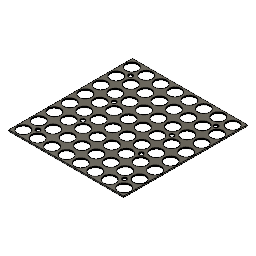
8x8_pcb_mask (Autodesk Fusion 360 design; units mm, degrees)
Autodesk Fusion 360 part; units mm, degrees
(part 1 of 18)
sketch "8x8-User_Comments" plane through (0, 0, 0) normal (0, 0, 1) x (1, 0, 0)
  line L0 (60.8107, -104.03) -> (61.1472, -104.007)
  line L1 (151.386, -103.077) -> (151.151, -103.327)
  line L2 (148.966, -104.174) -> (148.623, -104.148)
  line L3 (58.4649, -102.896) -> (58.6866, -103.15)
  line L4 (151.941, -100.763) -> (151.883, -100.431)
  line L5 (152.029, -100.419) -> (152.086, -100.757)
  line L6 (57.7053, -101.057) -> (57.7087, -101.008)
  line L7 (149.732, -98.1062) -> (150.062, -98.2032)
  line L8 (147.186, -103.377) -> (147.46, -103.574)
  line L9 (149.397, -104.007) -> (149.729, -103.945)
  line L10 (63.1322, -102.847) -> (63.3174, -102.565)
  line L11 (150.605, -103.741) -> (150.3, -103.9)
  line L12 (57.7292, -100.715) -> (57.7912, -100.377)
  line L13 (149.061, -104.03) -> (149.397, -104.007)
  line L14 (150.36, -103.711) -> (150.651, -103.54)
  line L15 (149.051, -98.0251) -> (149.394, -98.0466)
  line L16 (59.8164, -103.867) -> (60.1409, -103.959)
  line L17 (146.879, -98.903) -> (147.137, -98.6769)
  line L18 (146.937, -103.15) -> (147.186, -103.377)
  line L19 (147.46, -103.574) -> (147.755, -103.738)
  line L20 (149.648, -104.112) -> (149.309, -104.162)
  line L21 (146.243, -102.005) -> (146.366, -102.32)
  line L22 (63.7042, -101.284) -> (63.71, -101.1)
  line L23 (147.644, -103.845) -> (147.346, -103.673)
  line L24 (63.71, -101.1) -> (63.6905, -100.763)
  line L25 (152.086, -100.757) -> (152.105, -101.1)
  line L26 (148.066, -103.867) -> (148.391, -103.959)
  line L27 (57.9886, -102.39) -> (57.8622, -102.071)
  line L28 (146.524, -102.618) -> (146.715, -102.896)
  line L29 (150.957, -98.7035) -> (151.212, -98.9333)
  line L30 (60.1409, -103.959) -> (60.4737, -104.014)
  line L31 (62.4014, -103.54) -> (62.6712, -103.338)
  line L32 (146.445, -99.4342) -> (146.647, -99.1565)
  line L33 (59.2101, -103.574) -> (59.5048, -103.738)
  line L34 (151.638, -99.4705) -> (151.803, -99.7713)
  line L35 (151.765, -102.506) -> (151.591, -102.802)
  line L36 (58.3437, -102.976) -> (58.1498, -102.693)
  line L37 (149.729, -103.945) -> (150.051, -103.846)
  line L38 (146.715, -102.896) -> (146.937, -103.15)
  line L39 (147.958, -103.982) -> (147.644, -103.845)
  line L40 (63.3174, -102.565) -> (63.469, -102.264)
  line L41 (61.9717, -98.4234) -> (61.6562, -98.3041)
  line L42 (152.104, -101.186) -> (152.075, -101.528)
  line L43 (57.8515, -101.008) -> (57.8603, -101.345)
  line L44 (151.567, -102.565) -> (151.719, -102.264)
  line L45 (150.921, -103.338) -> (151.166, -103.106)
  line L46 (57.8622, -102.071) -> (57.7722, -101.739)
  line L47 (145.955, -101.057) -> (145.959, -101.008)
  line L48 (150.062, -98.2032) -> (150.378, -98.3362)
  line L49 (146.818, -103.236) -> (146.594, -102.976)
  line L50 (60.3217, -98.2061) -> (59.9921, -98.278)
  line L51 (62.1102, -103.711) -> (62.4014, -103.54)
  line L52 (58.1978, -99.7154) -> (58.0558, -100.021)
  line L53 (63.469, -102.264) -> (63.5849, -101.947)
  line L54 (151.954, -101.284) -> (151.96, -101.1)
  line L55 (146.022, -101.739) -> (145.97, -101.4)
  line L56 (150.889, -103.549) -> (150.605, -103.741)
  line L57 (59.9921, -98.278) -> (59.6729, -98.3872)
  line L58 (150.378, -98.3362) -> (150.678, -98.5037)
  line L59 (146.647, -99.1565) -> (146.879, -98.903)
  line L60 (146.366, -102.32) -> (146.524, -102.618)
  line L61 (147.755, -103.738) -> (148.066, -103.867)
  line L62 (58.8195, -98.9226) -> (58.5822, -99.1624)
  line L63 (57.9078, -101.679) -> (57.9934, -102.005)
  line L64 (57.8815, -100.672) -> (57.8515, -101.008)
  line L65 (151.96, -101.1) -> (151.941, -100.763)
  line L66 (61.4789, -103.945) -> (61.8013, -103.846)
  line L67 (145.959, -101.008) -> (145.979, -100.715)
  line L68 (150.651, -103.54) -> (150.921, -103.338)
  line L69 (63.4044, -99.7972) -> (63.2373, -99.5042)
  line L70 (62.2715, -98.5781) -> (61.9717, -98.4234)
  line L71 (148.37, -98.0967) -> (148.709, -98.0418)
  line L72 (151.787, -100.108) -> (151.654, -99.7972)
  line L73 (146.14, -100.048) -> (146.276, -99.7327)
  line L74 (152.105, -101.1) -> (152.104, -101.186)
  line L75 (147.346, -103.673) -> (147.07, -103.469)
  line L76 (63.0376, -99.2324) -> (62.8079, -98.9853)
  line L77 (150.3, -103.9) -> (149.98, -104.024)
  line L78 (147.07, -103.469) -> (146.818, -103.236)
  line L79 (148.709, -98.0418) -> (149.051, -98.0251)
  line L80 (151.591, -102.802) -> (151.386, -103.077)
  line L81 (148.391, -103.959) -> (148.724, -104.014)
  line L82 (58.0558, -100.021) -> (57.9499, -100.342)
  line L83 (59.3685, -98.5325) -> (59.0827, -98.7117)
  line L84 (146.239, -102.39) -> (146.112, -102.071)
  line L85 (146.4, -102.693) -> (146.239, -102.39)
  line L86 (58.116, -102.32) -> (58.2738, -102.618)
  line L87 (148.724, -104.014) -> (149.061, -104.03)
  line L88 (146.041, -100.377) -> (146.14, -100.048)
  line L89 (58.6866, -103.15) -> (58.9361, -103.377)
  line L90 (59.5048, -103.738) -> (59.8164, -103.867)
  line L91 (147.137, -98.6769) -> (147.419, -98.4809)
  line L92 (59.6729, -98.3872) -> (59.3685, -98.5325)
  line L93 (149.394, -98.0466) -> (149.732, -98.1062)
  line L94 (60.9946, -98.1779) -> (60.6573, -98.1726)
  line L95 (151.914, -101.619) -> (151.954, -101.284)
  line L96 (57.7722, -101.739) -> (57.7197, -101.4)
  line L97 (146.594, -102.976) -> (146.4, -102.693)
  line L98 (151.934, -100.089) -> (152.029, -100.419)
  line L99 (58.1498, -102.693) -> (57.9886, -102.39)
  line L100 (63.6905, -100.763) -> (63.6325, -100.431)
  line L101 (151.151, -103.327) -> (150.889, -103.549)
  line L102 (62.6712, -103.338) -> (62.9158, -103.106)
  line L103 (151.44, -99.19) -> (151.638, -99.4705)
  line L104 (63.2373, -99.5042) -> (63.0376, -99.2324)
  line L105 (57.9934, -102.005) -> (58.116, -102.32)
  line L106 (148.623, -104.148) -> (148.286, -104.084)
  line L107 (150.678, -98.5037) -> (150.957, -98.7035)
  line L108 (151.719, -102.264) -> (151.835, -101.947)
  line L109 (151.212, -98.9333) -> (151.44, -99.19)
  line L110 (146.112, -102.071) -> (146.022, -101.739)
  line L111 (60.4737, -104.014) -> (60.8107, -104.03)
  line L112 (152.008, -101.865) -> (151.905, -102.192)
  line L113 (58.2738, -102.618) -> (58.4649, -102.896)
  line L114 (152.075, -101.528) -> (152.008, -101.865)
  line L115 (145.97, -101.4) -> (145.955, -101.057)
  line L116 (63.5849, -101.947) -> (63.6637, -101.619)
  line L117 (63.6325, -100.431) -> (63.5367, -100.108)
  line L118 (151.905, -102.192) -> (151.765, -102.506)
  line L119 (63.5367, -100.108) -> (63.4044, -99.7972)
  line L120 (57.8603, -101.345) -> (57.9078, -101.679)
  line L121 (148.286, -104.084) -> (147.958, -103.982)
  line L122 (147.721, -98.3177) -> (148.039, -98.1891)
  line L123 (60.6573, -98.1726) -> (60.3217, -98.2061)
  line L124 (148.039, -98.1891) -> (148.37, -98.0967)
  line L125 (146.276, -99.7327) -> (146.445, -99.4342)
  line L126 (149.98, -104.024) -> (149.648, -104.112)
  line L127 (151.835, -101.947) -> (151.914, -101.619)
  line L128 (151.883, -100.431) -> (151.787, -100.108)
  line L129 (62.5514, -98.7662) -> (62.2715, -98.5781)
  line L130 (58.5822, -99.1624) -> (58.3741, -99.4278)
  line L131 (151.166, -103.106) -> (151.382, -102.847)
  line L132 (58.3741, -99.4278) -> (58.1978, -99.7154)
  line L133 (62.9158, -103.106) -> (63.1322, -102.847)
  line L134 (149.309, -104.162) -> (148.966, -104.174)
  line L135 (145.979, -100.715) -> (146.041, -100.377)
  line L136 (61.1472, -104.007) -> (61.4789, -103.945)
  line L137 (146.158, -101.679) -> (146.243, -102.005)
  line L138 (147.419, -98.4809) -> (147.721, -98.3177)
  line L139 (63.6637, -101.619) -> (63.7042, -101.284)
  line L140 (58.9361, -103.377) -> (59.2101, -103.574)
  line L141 (151.382, -102.847) -> (151.567, -102.565)
  line L142 (57.9499, -100.342) -> (57.8815, -100.672)
  line L143 (61.6562, -98.3041) -> (61.329, -98.2219)
  line L144 (61.329, -98.2219) -> (60.9946, -98.1779)
  line L145 (151.803, -99.7713) -> (151.934, -100.089)
  line L146 (150.051, -103.846) -> (150.36, -103.711)
  line L147 (62.8079, -98.9853) -> (62.5514, -98.7662)
  line L148 (57.7087, -101.008) -> (57.7292, -100.715)
  line L149 (61.8013, -103.846) -> (62.1102, -103.711)
  line L150 (59.0827, -98.7117) -> (58.8195, -98.9226)
  line L151 (57.7197, -101.4) -> (57.7053, -101.057)
  line L152 (169.271, -52.4277) -> (169.589, -52.2991)
  line L153 (172.155, -57.8513) -> (171.85, -58.0104)
  line L154 (167.591, -54.4869) -> (167.69, -54.1583)
  line L155 (172.936, -57.1866) -> (172.701, -57.4368)
  line L156 (150.801, -98.7662) -> (150.521, -98.5781)
  line L157 (148.242, -98.278) -> (147.923, -98.3872)
  line L158 (167.505, -55.1671) -> (167.509, -55.118)
  line L159 (173.654, -55.2959) -> (173.625, -55.638)
  line L160 (173.484, -54.1987) -> (173.579, -54.5287)
  line L161 (151.288, -99.2324) -> (151.058, -98.9853)
  line L162 (146.306, -100.021) -> (146.2, -100.342)
  line L163 (169.508, -58.0921) -> (169.194, -57.9547)
  line L164 (173.353, -53.8813) -> (173.484, -54.1987)
  line L165 (150.521, -98.5781) -> (150.222, -98.4234)
  line L166 (170.173, -58.258) -> (169.836, -58.1937)
  line L167 (171.612, -52.3132) -> (171.928, -52.4462)
  line L168 (167.662, -56.1806) -> (167.572, -55.8493)
  line L169 (173.558, -55.9747) -> (173.455, -56.302)
  line L170 (171.53, -58.1345) -> (171.198, -58.2222)
  line L171 (167.995, -53.5442) -> (168.197, -53.2665)
  line L172 (169.194, -57.9547) -> (168.896, -57.783)
  line L173 (149.906, -98.3041) -> (149.579, -98.2219)
  line L174 (168.969, -52.5909) -> (169.271, -52.4277)
  line L175 (146.448, -99.7154) -> (146.306, -100.021)
  line L176 (168.197, -53.2665) -> (168.429, -53.013)
  line L177 (168.687, -52.7869) -> (168.969, -52.5909)
  line L178 (149.245, -98.1779) -> (148.907, -98.1726)
  line L179 (167.69, -54.1583) -> (167.826, -53.8427)
  line L180 (171.198, -58.2222) -> (170.859, -58.2723)
  line L181 (171.928, -52.4462) -> (172.228, -52.6137)
  line L182 (170.259, -52.1518) -> (170.601, -52.1351)
  line L183 (172.507, -52.8135) -> (172.762, -53.0433)
  line L184 (167.95, -56.8029) -> (167.789, -56.4998)
  line L185 (173.579, -54.5287) -> (173.636, -54.8672)
  line L186 (172.99, -53.3) -> (173.188, -53.5805)
  line L187 (146.2, -100.342) -> (146.131, -100.672)
  line L188 (167.793, -56.1154) -> (167.916, -56.4297)
  line L189 (148.907, -98.1726) -> (148.572, -98.2061)
  line L190 (147.923, -98.3872) -> (147.618, -98.5325)
  line L191 (146.832, -99.1624) -> (146.624, -99.4278)
  line L192 (170.516, -58.2843) -> (170.173, -58.258)
  line L193 (173.188, -53.5805) -> (173.353, -53.8813)
  line L194 (173.315, -56.6156) -> (173.141, -56.9117)
  line L195 (173.625, -55.638) -> (173.558, -55.9747)
  line L196 (167.572, -55.8493) -> (167.52, -55.5101)
  line L197 (173.655, -55.21) -> (173.654, -55.2959)
  line L198 (167.826, -53.8427) -> (167.995, -53.5442)
  line L199 (167.916, -56.4297) -> (168.074, -56.7278)
  line L200 (146.624, -99.4278) -> (146.448, -99.7154)
  line L201 (171.85, -58.0104) -> (171.53, -58.1345)
  line L202 (150.222, -98.4234) -> (149.906, -98.3041)
  line L203 (172.762, -53.0433) -> (172.99, -53.3)
  line L204 (167.708, -55.7891) -> (167.793, -56.1154)
  line L205 (151.058, -98.9853) -> (150.801, -98.7662)
  line L206 (167.789, -56.4998) -> (167.662, -56.1806)
  line L207 (168.144, -57.0862) -> (167.95, -56.8029)
  line L208 (168.265, -57.0058) -> (168.487, -57.26)
  line L209 (169.836, -58.1937) -> (169.508, -58.0921)
  line L210 (168.62, -57.5793) -> (168.368, -57.3461)
  line L211 (146.131, -100.672) -> (146.101, -101.008)
  line L212 (170.601, -52.1351) -> (170.944, -52.1566)
  line L213 (168.896, -57.783) -> (168.62, -57.5793)
  line L214 (146.11, -101.345) -> (146.158, -101.679)
  line L215 (147.333, -98.7117) -> (147.069, -98.9226)
  line L216 (168.074, -56.7278) -> (168.265, -57.0058)
  line L217 (168.429, -53.013) -> (168.687, -52.7869)
  line L218 (173.636, -54.8672) -> (173.655, -55.21)
  line L219 (149.579, -98.2219) -> (149.245, -98.1779)
  line L220 (172.439, -57.6593) -> (172.155, -57.8513)
  line L221 (147.618, -98.5325) -> (147.333, -98.7117)
  line L222 (168.368, -57.3461) -> (168.144, -57.0862)
  line L223 (151.487, -99.5042) -> (151.288, -99.2324)
  line L224 (169.92, -52.2067) -> (170.259, -52.1518)
  line L225 (151.654, -99.7972) -> (151.487, -99.5042)
  line L226 (167.52, -55.5101) -> (167.505, -55.1671)
  line L227 (148.572, -98.2061) -> (148.242, -98.278)
  line L228 (147.069, -98.9226) -> (146.832, -99.1624)
  line L229 (167.529, -54.8246) -> (167.591, -54.4869)
  line L230 (146.101, -101.008) -> (146.11, -101.345)
  line L231 (169.589, -52.2991) -> (169.92, -52.2067)
  line L232 (172.228, -52.6137) -> (172.507, -52.8135)
  line L233 (172.701, -57.4368) -> (172.439, -57.6593)
  line L234 (171.282, -52.2162) -> (171.612, -52.3132)
  line L235 (170.944, -52.1566) -> (171.282, -52.2162)
  line L236 (167.509, -55.118) -> (167.529, -54.8246)
  line L237 (173.455, -56.302) -> (173.315, -56.6156)
  line L238 (170.859, -58.2723) -> (170.516, -58.2843)
  line L239 (173.141, -56.9117) -> (172.936, -57.1866)
  line L240 (173.51, -55.21) -> (173.491, -54.8732)
  line L241 (168.736, -57.487) -> (169.01, -57.6838)
  line L242 (172.838, -53.3424) -> (172.608, -53.0953)
  line L243 (172.608, -53.0953) -> (172.351, -52.8762)
  line L244 (173.491, -54.8732) -> (173.433, -54.5409)
  line L245 (168.487, -57.26) -> (168.736, -57.487)
  line L246 (173.269, -56.3736) -> (173.385, -56.0569)
  line L247 (169.01, -57.6838) -> (169.305, -57.8479)
  line L248 (172.201, -57.6504) -> (172.471, -57.4479)
  line L249 (172.716, -57.2157) -> (172.932, -56.9569)
  line L250 (173.464, -55.7289) -> (173.504, -55.394)
  line L251 (173.504, -55.394) -> (173.51, -55.21)
  line L252 (172.471, -57.4479) -> (172.716, -57.2157)
  line L253 (173.117, -56.675) -> (173.269, -56.3736)
  line L254 (171.601, -57.9562) -> (171.91, -57.8206)
  line L255 (173.385, -56.0569) -> (173.464, -55.7289)
  line L256 (169.305, -57.8479) -> (169.616, -57.977)
  line L257 (172.071, -52.6881) -> (171.772, -52.5334)
  line L258 (172.932, -56.9569) -> (173.117, -56.675)
  line L259 (173.337, -54.2175) -> (173.204, -53.9072)
  line L260 (173.204, -53.9072) -> (173.037, -53.6142)
  line L261 (171.91, -57.8206) -> (172.201, -57.6504)
  line L262 (170.611, -58.1398) -> (170.947, -58.1169)
  line L263 (169.941, -58.0694) -> (170.274, -58.1239)
  line L264 (170.274, -58.1239) -> (170.611, -58.1398)
  line L265 (173.433, -54.5409) -> (173.337, -54.2175)
  line L266 (170.947, -58.1169) -> (171.279, -58.0554)
  line L267 (172.351, -52.8762) -> (172.071, -52.6881)
  line L268 (169.616, -57.977) -> (169.941, -58.0694)
  line L269 (173.037, -53.6142) -> (172.838, -53.3424)
  line L270 (171.279, -58.0554) -> (171.601, -57.9562)
  line L271 (63.1356, -103.077) -> (62.9006, -103.327)
  line L272 (63.5531, -99.7713) -> (63.684, -100.089)
  line L273 (61.7302, -104.024) -> (61.3983, -104.112)
  line L274 (63.7584, -101.865) -> (63.6546, -102.192)
  line L275 (58.8199, -103.469) -> (58.568, -103.236)
  line L276 (59.0962, -103.673) -> (58.8199, -103.469)
  line L277 (58.568, -103.236) -> (58.3437, -102.976)
  line L278 (59.3936, -103.845) -> (59.0962, -103.673)
  line L279 (63.855, -101.1) -> (63.8538, -101.186)
  line L280 (63.6546, -102.192) -> (63.515, -102.506)
  line L281 (62.0503, -103.9) -> (61.7302, -104.024)
  line L282 (60.0361, -104.084) -> (59.7081, -103.982)
  line L283 (62.9006, -103.327) -> (62.6391, -103.549)
  line L284 (63.8358, -100.757) -> (63.855, -101.1)
  line L285 (63.8538, -101.186) -> (63.8251, -101.528)
  line L286 (60.7156, -104.174) -> (60.3733, -104.148)
  line L287 (59.7081, -103.982) -> (59.3936, -103.845)
  line L288 (60.3733, -104.148) -> (60.0361, -104.084)
  line L289 (63.684, -100.089) -> (63.7786, -100.419)
  line L290 (63.3412, -102.802) -> (63.1356, -103.077)
  line L291 (63.8251, -101.528) -> (63.7584, -101.865)
  line L292 (62.3545, -103.741) -> (62.0503, -103.9)
  line L293 (61.3983, -104.112) -> (61.0587, -104.162)
  line L294 (61.0587, -104.162) -> (60.7156, -104.174)
  line L295 (63.515, -102.506) -> (63.3412, -102.802)
  line L296 (63.7786, -100.419) -> (63.8358, -100.757)
  line L297 (62.6391, -103.549) -> (62.3545, -103.741)
  line L298 (37.7797, -50.8267) -> (38.1186, -50.7718)
  line L299 (39.1422, -50.8362) -> (39.4715, -50.9332)
  line L300 (36.8287, -51.2109) -> (37.1307, -51.0477)
  line L301 (167.856, -54.1314) -> (167.75, -54.4517)
  line L302 (35.6857, -52.4627) -> (35.8553, -52.1642)
  line L303 (167.75, -54.4517) -> (167.681, -54.782)
  line L304 (39.0583, -56.8422) -> (38.7187, -56.8923)
  line L305 (40.7956, -55.8066) -> (40.5606, -56.0568)
  line L306 (36.2885, -51.633) -> (36.5468, -51.4069)
  line L307 (41.2131, -52.5013) -> (41.344, -52.8187)
  line L308 (41.4386, -53.1487) -> (41.4958, -53.4872)
  line L309 (171.772, -52.5334) -> (171.456, -52.4141)
  line L310 (171.456, -52.4141) -> (171.129, -52.3319)
  line L311 (168.382, -53.2724) -> (168.174, -53.5378)
  line L312 (35.5504, -52.7783) -> (35.6857, -52.4627)
  line L313 (168.174, -53.5378) -> (167.998, -53.8254)
  line L314 (40.8499, -51.92) -> (41.0477, -52.2005)
  line L315 (41.0012, -55.5317) -> (40.7956, -55.8066)
  line L316 (168.883, -52.8217) -> (168.619, -53.0326)
  line L317 (40.2991, -56.2793) -> (40.0145, -56.4713)
  line L318 (169.792, -52.388) -> (169.473, -52.4972)
  line L319 (40.5606, -56.0568) -> (40.2991, -56.2793)
  line L320 (168.619, -53.0326) -> (168.382, -53.2724)
  line L321 (170.795, -52.2879) -> (170.457, -52.2826)
  line L322 (41.4851, -54.258) -> (41.4184, -54.5947)
  line L323 (39.3902, -56.7545) -> (39.0583, -56.8422)
  line L324 (37.449, -50.9191) -> (37.7797, -50.8267)
  line L325 (41.5138, -53.9159) -> (41.4851, -54.258)
  line L326 (40.6219, -51.6632) -> (40.8499, -51.92)
  line L327 (37.1307, -51.0477) -> (37.449, -50.9191)
  line L328 (35.8553, -52.1642) -> (36.057, -51.8865)
  line L329 (36.057, -51.8865) -> (36.2885, -51.633)
  line L330 (41.175, -55.2356) -> (41.0012, -55.5317)
  line L331 (40.3668, -51.4335) -> (40.6219, -51.6632)
  line L332 (170.457, -52.2826) -> (170.122, -52.3161)
  line L333 (41.0477, -52.2005) -> (41.2131, -52.5013)
  line L334 (167.681, -54.782) -> (167.651, -55.118)
  line L335 (38.8041, -50.7766) -> (39.1422, -50.8362)
  line L336 (41.344, -52.8187) -> (41.4386, -53.1487)
  line L337 (167.998, -53.8254) -> (167.856, -54.1314)
  line L338 (39.7103, -56.6304) -> (39.3902, -56.7545)
  line L339 (38.1186, -50.7718) -> (38.4615, -50.7551)
  line L340 (41.3146, -54.922) -> (41.175, -55.2356)
  line L341 (36.5468, -51.4069) -> (36.8287, -51.2109)
  line L342 (40.0877, -51.2337) -> (40.3668, -51.4335)
  line L343 (41.4958, -53.4872) -> (41.515, -53.83)
  line L344 (167.66, -55.4552) -> (167.708, -55.7891)
  line L345 (39.788, -51.0662) -> (40.0877, -51.2337)
  line L346 (169.473, -52.4972) -> (169.168, -52.6425)
  line L347 (169.168, -52.6425) -> (168.883, -52.8217)
  line L348 (40.0145, -56.4713) -> (39.7103, -56.6304)
  line L349 (39.4715, -50.9332) -> (39.788, -51.0662)
  line L350 (167.651, -55.118) -> (167.66, -55.4552)
  line L351 (41.4184, -54.5947) -> (41.3146, -54.922)
  line L352 (170.122, -52.3161) -> (169.792, -52.388)
  line L353 (38.4615, -50.7551) -> (38.8041, -50.7766)
  line L354 (171.129, -52.3319) -> (170.795, -52.2879)
  line L355 (41.515, -53.83) -> (41.5138, -53.9159)
  line L356 (35.4512, -53.1069) -> (35.5504, -52.7783)
  line L357 (148.889, -146.019) -> (149.22, -145.927)
  line L358 (150.756, -146.134) -> (150.429, -146.052)
  line L359 (61.0573, -146.453) -> (60.7217, -146.486)
  line L360 (59.2195, -147.203) -> (58.9822, -147.442)
  line L361 (150.159, -151.992) -> (149.816, -152.004)
  line L362 (148.31, -151.404) -> (148.605, -151.568)
  line L363 (147.295, -147.264) -> (147.497, -146.987)
  line L364 (152.062, -146.763) -> (152.29, -147.02)
  line L365 (146.872, -149.569) -> (146.82, -149.23)
  line L366 (61.3946, -146.458) -> (61.0573, -146.453)
  line L367 (150.244, -145.877) -> (150.582, -145.936)
  line L368 (152.016, -150.936) -> (152.232, -150.677)
  line L369 (147.987, -146.507) -> (148.269, -146.311)
  line L370 (60.7217, -146.486) -> (60.3921, -146.558)
  line L371 (64.0905, -149.043) -> (64.0325, -148.711)
  line L372 (63.2079, -147.265) -> (62.9514, -147.046)
  line L373 (152.488, -147.3) -> (152.653, -147.601)
  line L374 (63.6373, -147.784) -> (63.4376, -147.512)
  line L375 (147.216, -150.15) -> (147.374, -150.448)
  line L376 (151.228, -146.166) -> (151.528, -146.334)
  line L377 (152.138, -147.062) -> (151.908, -146.815)
  line L378 (151.651, -146.596) -> (151.371, -146.408)
  line L379 (151.501, -151.37) -> (151.771, -151.168)
  line L380 (146.805, -148.887) -> (146.809, -148.838)
  line L381 (149.911, -151.86) -> (150.247, -151.837)
  line L382 (60.3921, -146.558) -> (60.0729, -146.667)
  line L383 (148.808, -151.812) -> (148.494, -151.675)
  line L384 (147.126, -147.563) -> (147.295, -147.264)
  line L385 (58.5978, -147.995) -> (58.4558, -148.301)
  line L386 (58.2603, -149.625) -> (58.3078, -149.959)
  line L387 (152.504, -147.627) -> (152.337, -147.334)
  line L388 (62.9514, -147.046) -> (62.6715, -146.858)
  line L389 (152.81, -148.93) -> (152.791, -148.593)
  line L390 (149.757, -146.003) -> (149.422, -146.036)
  line L391 (151.15, -151.73) -> (150.83, -151.854)
  line L392 (61.729, -146.502) -> (61.3946, -146.458)
  line L393 (152.784, -147.919) -> (152.879, -148.249)
  line L394 (149.241, -151.789) -> (149.574, -151.844)
  line L395 (149.422, -146.036) -> (149.092, -146.108)
  line L396 (148.269, -146.311) -> (148.571, -146.148)
  line L397 (58.2515, -149.288) -> (58.2603, -149.625)
  line L398 (152.29, -147.02) -> (152.488, -147.3)
  line L399 (147.92, -151.299) -> (147.668, -151.066)
  line L400 (149.473, -151.978) -> (149.136, -151.914)
  line L401 (148.196, -151.503) -> (147.92, -151.299)
  line L402 (148.468, -146.362) -> (148.183, -146.542)
  line L403 (150.429, -146.052) -> (150.095, -146.008)
  line L404 (58.7741, -147.708) -> (58.5978, -147.995)
  line L405 (152.858, -149.695) -> (152.755, -150.022)
  line L406 (150.912, -146.033) -> (151.228, -146.166)
  line L407 (148.605, -151.568) -> (148.916, -151.697)
  line L408 (146.809, -148.838) -> (146.829, -148.545)
  line L409 (147.25, -150.523) -> (147.089, -150.22)
  line L410 (149.559, -145.872) -> (149.901, -145.855)
  line L411 (149.136, -151.914) -> (148.808, -151.812)
  line L412 (147.474, -147.258) -> (147.298, -147.545)
  line L413 (63.9367, -148.388) -> (63.8044, -148.077)
  line L414 (152.615, -150.336) -> (152.441, -150.632)
  line L415 (150.095, -146.008) -> (149.757, -146.003)
  line L416 (149.574, -151.844) -> (149.911, -151.86)
  line L417 (146.829, -148.545) -> (146.891, -148.207)
  line L418 (152.955, -148.93) -> (152.954, -149.016)
  line L419 (59.7685, -146.812) -> (59.4827, -146.992)
  line L420 (62.3717, -146.703) -> (62.0562, -146.584)
  line L421 (149.22, -145.927) -> (149.559, -145.872)
  line L422 (152.954, -149.016) -> (152.925, -149.358)
  line L423 (151.739, -151.379) -> (151.455, -151.571)
  line L424 (152.001, -151.157) -> (151.739, -151.379)
  line L425 (62.6715, -146.858) -> (62.3717, -146.703)
  line L426 (147.156, -147.851) -> (147.05, -148.172)
  line L427 (152.236, -150.907) -> (152.001, -151.157)
  line L428 (152.337, -147.334) -> (152.138, -147.062)
  line L429 (148.773, -146.217) -> (148.468, -146.362)
  line L430 (59.4827, -146.992) -> (59.2195, -147.203)
  line L431 (152.804, -149.114) -> (152.81, -148.93)
  line L432 (62.0562, -146.584) -> (61.729, -146.502)
  line L433 (63.8044, -148.077) -> (63.6373, -147.784)
  line L434 (148.183, -146.542) -> (147.919, -146.753)
  line L435 (147.919, -146.753) -> (147.682, -146.992)
  line L436 (151.528, -146.334) -> (151.807, -146.534)
  line L437 (148.916, -151.697) -> (149.241, -151.789)
  line L438 (147.444, -150.806) -> (147.25, -150.523)
  line L439 (58.9822, -147.442) -> (58.7741, -147.708)
  line L440 (151.21, -151.541) -> (151.501, -151.37)
  line L441 (64.0325, -148.711) -> (63.9367, -148.388)
  line L442 (147.668, -151.066) -> (147.444, -150.806)
  line L443 (152.417, -150.395) -> (152.569, -150.094)
  line L444 (150.498, -151.942) -> (150.159, -151.992)
  line L445 (58.3499, -148.622) -> (58.2815, -148.952)
  line L446 (149.816, -152.004) -> (149.473, -151.978)
  line L447 (148.494, -151.675) -> (148.196, -151.503)
  line L448 (148.036, -151.207) -> (148.31, -151.404)
  line L449 (64.11, -149.38) -> (64.0905, -149.043)
  line L450 (147.374, -150.448) -> (147.565, -150.726)
  line L451 (152.755, -150.022) -> (152.615, -150.336)
  line L452 (63.4376, -147.512) -> (63.2079, -147.265)
  line L453 (151.455, -151.571) -> (151.15, -151.73)
  line L454 (151.807, -146.534) -> (152.062, -146.763)
  line L455 (147.729, -146.733) -> (147.987, -146.507)
  line L456 (151.072, -146.253) -> (150.756, -146.134)
  line L457 (146.891, -148.207) -> (146.99, -147.878)
  line L458 (147.298, -147.545) -> (147.156, -147.851)
  line L459 (152.791, -148.593) -> (152.733, -148.261)
  line L460 (152.685, -149.777) -> (152.764, -149.449)
  line L461 (147.089, -150.22) -> (146.962, -149.901)
  line L462 (152.733, -148.261) -> (152.637, -147.938)
  line L463 (152.441, -150.632) -> (152.236, -150.907)
  line L464 (150.582, -145.936) -> (150.912, -146.033)
  line L465 (151.908, -146.815) -> (151.651, -146.596)
  line L466 (147.093, -149.835) -> (147.216, -150.15)
  line L467 (147.565, -150.726) -> (147.787, -150.98)
  line L468 (146.99, -147.878) -> (147.126, -147.563)
  line L469 (150.83, -151.854) -> (150.498, -151.942)
  line L470 (147.008, -149.509) -> (147.093, -149.835)
  line L471 (152.764, -149.449) -> (152.804, -149.114)
  line L472 (152.569, -150.094) -> (152.685, -149.777)
  line L473 (146.82, -149.23) -> (146.805, -148.887)
  line L474 (149.901, -145.855) -> (150.244, -145.877)
  line L475 (152.637, -147.938) -> (152.504, -147.627)
  line L476 (151.771, -151.168) -> (152.016, -150.936)
  line L477 (152.879, -148.249) -> (152.936, -148.587)
  line L478 (150.247, -151.837) -> (150.579, -151.775)
  line L479 (151.371, -146.408) -> (151.072, -146.253)
  line L480 (146.962, -149.901) -> (146.872, -149.569)
  line L481 (150.901, -151.676) -> (151.21, -151.541)
  line L482 (147.787, -150.98) -> (148.036, -151.207)
  line L483 (152.925, -149.358) -> (152.858, -149.695)
  line L484 (147.497, -146.987) -> (147.729, -146.733)
  line L485 (60.0729, -146.667) -> (59.7685, -146.812)
  line L486 (58.2815, -148.952) -> (58.2515, -149.288)
  line L487 (58.4558, -148.301) -> (58.3499, -148.622)
  line L488 (152.232, -150.677) -> (152.417, -150.395)
  line L489 (150.579, -151.775) -> (150.901, -151.676)
  line L490 (148.571, -146.148) -> (148.889, -146.019)
  line L491 (149.092, -146.108) -> (148.773, -146.217)
  line L492 (152.936, -148.587) -> (152.955, -148.93)
  line L493 (147.682, -146.992) -> (147.474, -147.258)
  line L494 (152.653, -147.601) -> (152.784, -147.919)
  line L495 (146.981, -148.502) -> (146.951, -148.838)
  line L496 (147.05, -148.172) -> (146.981, -148.502)
  line L497 (58.8868, -98.6769) -> (59.1687, -98.4809)
  line L498 (59.4707, -98.3177) -> (59.789, -98.1891)
  line L499 (61.8115, -98.2032) -> (62.128, -98.3362)
  line L500 (58.6285, -98.903) -> (58.8868, -98.6769)
  line L501 (62.4277, -98.5037) -> (62.7068, -98.7035)
  line L502 (62.7068, -98.7035) -> (62.9619, -98.9333)
  line L503 (58.397, -99.1565) -> (58.6285, -98.903)
  line L504 (57.8904, -100.048) -> (58.0257, -99.7327)
  line L505 (62.9619, -98.9333) -> (63.1899, -99.19)
  line L506 (60.1197, -98.0967) -> (60.4586, -98.0418)
  line L507 (146.951, -148.838) -> (146.96, -149.175)
  line L508 (61.4822, -98.1062) -> (61.8115, -98.2032)
  line L509 (58.0257, -99.7327) -> (58.1953, -99.4342)
  line L510 (60.8015, -98.0251) -> (61.1441, -98.0466)
  line L511 (59.1687, -98.4809) -> (59.4707, -98.3177)
  line L512 (63.3877, -99.4705) -> (63.5531, -99.7713)
  line L513 (61.1441, -98.0466) -> (61.4822, -98.1062)
  line L514 (63.1899, -99.19) -> (63.3877, -99.4705)
  line L515 (60.4586, -98.0418) -> (60.8015, -98.0251)
  line L516 (59.789, -98.1891) -> (60.1197, -98.0967)
  line L517 (58.1953, -99.4342) -> (58.397, -99.1565)
  line L518 (146.96, -149.175) -> (147.008, -149.509)
  line L519 (62.128, -98.3362) -> (62.4277, -98.5037)
  line L520 (57.7912, -100.377) -> (57.8904, -100.048)
  line L521 (63.869, -150.544) -> (63.9849, -150.227)
  line L522 (63.9849, -150.227) -> (64.0637, -149.899)
  line L523 (63.3158, -151.386) -> (63.5322, -151.127)
  line L524 (59.6101, -151.854) -> (59.9048, -152.018)
  line L525 (64.1042, -149.564) -> (64.11, -149.38)
  line L526 (60.2164, -152.147) -> (60.5408, -152.239)
  line L527 (63.0712, -151.618) -> (63.3158, -151.386)
  line L528 (64.0637, -149.899) -> (64.1042, -149.564)
  line L529 (62.8014, -151.82) -> (63.0712, -151.618)
  line L530 (59.9048, -152.018) -> (60.2164, -152.147)
  line L531 (62.2013, -152.126) -> (62.5102, -151.991)
  line L532 (63.7174, -150.845) -> (63.869, -150.544)
  line L533 (61.5472, -152.287) -> (61.8789, -152.225)
  line L534 (61.8789, -152.225) -> (62.2013, -152.126)
  line L535 (63.5322, -151.127) -> (63.7174, -150.845)
  line L536 (62.5102, -151.991) -> (62.8014, -151.82)
  line L537 (61.2107, -152.31) -> (61.5472, -152.287)
  line L538 (60.8737, -152.294) -> (61.2107, -152.31)
  line L539 (60.5408, -152.239) -> (60.8737, -152.294)
  line L540 (58.2622, -150.351) -> (58.1722, -150.019)
  line L541 (58.3886, -150.67) -> (58.2622, -150.351)
  line L542 (58.1722, -150.019) -> (58.1197, -149.68)
  line L543 (58.1087, -149.288) -> (58.1292, -148.995)
  line L544 (59.3361, -151.657) -> (59.6101, -151.854)
  line L545 (58.6738, -150.898) -> (58.8649, -151.176)
  line L546 (58.1053, -149.337) -> (58.1087, -149.288)
  line L547 (58.1292, -148.995) -> (58.1912, -148.657)
  line L548 (59.0866, -151.43) -> (59.3361, -151.657)
  line L549 (58.3934, -150.285) -> (58.516, -150.6)
  line L550 (58.516, -150.6) -> (58.6738, -150.898)
  line L551 (58.1197, -149.68) -> (58.1053, -149.337)
  line L552 (58.3078, -149.959) -> (58.3934, -150.285)
  line L553 (58.8649, -151.176) -> (59.0866, -151.43)
  line L554 (58.5498, -150.973) -> (58.3886, -150.67)
  line L555 (167.71, -194.392) -> (167.641, -194.722)
  line L556 (64.1584, -150.145) -> (64.0546, -150.472)
  line L557 (64.2538, -149.466) -> (64.2251, -149.808)
  line L558 (63.9531, -148.051) -> (64.084, -148.369)
  line L559 (61.8822, -146.386) -> (62.2115, -146.483)
  line L560 (167.62, -195.395) -> (167.668, -195.729)
  line L561 (63.3006, -151.607) -> (63.0391, -151.829)
  line L562 (58.968, -151.516) -> (58.7437, -151.256)
  line L563 (63.1068, -146.984) -> (63.3619, -147.213)
  line L564 (63.7877, -147.75) -> (63.9531, -148.051)
  line L565 (64.084, -148.369) -> (64.1786, -148.699)
  line L566 (58.4257, -148.013) -> (58.5953, -147.714)
  line L567 (59.8707, -146.598) -> (60.189, -146.469)
  line L568 (63.7412, -151.082) -> (63.5356, -151.357)
  line L569 (59.0285, -147.183) -> (59.2868, -146.957)
  line L570 (63.5899, -147.47) -> (63.7877, -147.75)
  line L571 (63.3619, -147.213) -> (63.5899, -147.47)
  line L572 (59.5687, -146.761) -> (59.8707, -146.598)
  line L573 (61.4587, -152.442) -> (61.1156, -152.454)
  line L574 (64.1786, -148.699) -> (64.2358, -149.037)
  line L575 (61.5441, -146.327) -> (61.8822, -146.386)
  line L576 (167.958, -193.765) -> (167.816, -194.071)
  line L577 (58.5953, -147.714) -> (58.797, -147.437)
  line L578 (62.1302, -152.304) -> (61.7983, -152.392)
  line L579 (59.2868, -146.957) -> (59.5687, -146.761)
  line L580 (167.641, -194.722) -> (167.611, -195.058)
  line L581 (58.2904, -148.328) -> (58.4257, -148.013)
  line L582 (64.2251, -149.808) -> (64.1584, -150.145)
  line L583 (64.0546, -150.472) -> (63.915, -150.786)
  line L584 (61.1156, -152.454) -> (60.7733, -152.428)
  line L585 (60.7733, -152.428) -> (60.4361, -152.364)
  line L586 (62.528, -146.616) -> (62.8277, -146.784)
  line L587 (63.5356, -151.357) -> (63.3006, -151.607)
  line L588 (60.5197, -146.377) -> (60.8586, -146.322)
  line L589 (63.915, -150.786) -> (63.7412, -151.082)
  line L590 (62.4503, -152.18) -> (62.1302, -152.304)
  line L591 (58.7437, -151.256) -> (58.5498, -150.973)
  line L592 (59.7936, -152.125) -> (59.4962, -151.953)
  line L593 (63.0391, -151.829) -> (62.7545, -152.021)
  line L594 (62.8277, -146.784) -> (63.1068, -146.984)
  line L595 (61.7983, -152.392) -> (61.4587, -152.442)
  line L596 (59.2199, -151.749) -> (58.968, -151.516)
  line L597 (58.797, -147.437) -> (59.0285, -147.183)
  line L598 (60.4361, -152.364) -> (60.1081, -152.262)
  line L599 (60.8586, -146.322) -> (61.2015, -146.305)
  line L600 (167.816, -194.071) -> (167.71, -194.392)
  line L601 (62.2115, -146.483) -> (62.528, -146.616)
  line L602 (64.255, -149.38) -> (64.2538, -149.466)
  line L603 (59.4962, -151.953) -> (59.2199, -151.749)
  line L604 (62.7545, -152.021) -> (62.4503, -152.18)
  line L605 (60.189, -146.469) -> (60.5197, -146.377)
  line L606 (58.1912, -148.657) -> (58.2904, -148.328)
  line L607 (64.2358, -149.037) -> (64.255, -149.38)
  line L608 (61.2015, -146.305) -> (61.5441, -146.327)
  line L609 (167.611, -195.058) -> (167.62, -195.395)
  line L610 (60.1081, -152.262) -> (59.7936, -152.125)
  line L611 (40.8677, -193.604) -> (41.1468, -193.804)
  line L612 (36.3304, -195.148) -> (36.4657, -194.833)
  line L613 (38.1481, -199.082) -> (37.8336, -198.945)
  line L614 (41.7812, -197.902) -> (41.5756, -198.177)
  line L615 (41.6299, -194.29) -> (41.8277, -194.57)
  line L616 (37.008, -198.336) -> (36.7837, -198.076)
  line L617 (41.5756, -198.177) -> (41.3406, -198.427)
  line L618 (42.1984, -196.965) -> (42.0946, -197.292)
  line L619 (36.837, -194.257) -> (37.0685, -194.003)
  line L620 (42.2651, -196.628) -> (42.1984, -196.965)
  line L621 (40.568, -193.436) -> (40.8677, -193.604)
  line L622 (39.8383, -199.212) -> (39.4987, -199.262)
  line L623 (38.5597, -193.197) -> (38.8986, -193.142)
  line L624 (41.1468, -193.804) -> (41.4019, -194.033)
  line L625 (41.955, -197.606) -> (41.7812, -197.902)
  line L626 (38.229, -193.289) -> (38.5597, -193.197)
  line L627 (41.8277, -194.57) -> (41.9931, -194.871)
  line L628 (42.295, -196.2) -> (42.2938, -196.286)
  line L629 (41.9931, -194.871) -> (42.124, -195.189)
  line L630 (38.8133, -199.248) -> (38.4761, -199.184)
  line L631 (39.9222, -193.206) -> (40.2515, -193.303)
  line L632 (37.3268, -193.777) -> (37.6087, -193.581)
  line L633 (42.2186, -195.519) -> (42.2758, -195.857)
  line L634 (37.6087, -193.581) -> (37.9107, -193.418)
  line L635 (38.8986, -193.142) -> (39.2415, -193.125)
  line L636 (39.2415, -193.125) -> (39.5841, -193.147)
  line L637 (42.2938, -196.286) -> (42.2651, -196.628)
  line L638 (41.0791, -198.649) -> (40.7945, -198.841)
  line L639 (36.5898, -197.793) -> (36.4286, -197.49)
  line L640 (36.4286, -197.49) -> (36.3022, -197.171)
  line L641 (42.124, -195.189) -> (42.2186, -195.519)
  line L642 (40.2515, -193.303) -> (40.568, -193.436)
  line L643 (41.3406, -198.427) -> (41.0791, -198.649)
  line L644 (37.2599, -198.569) -> (37.008, -198.336)
  line L645 (36.4657, -194.833) -> (36.6353, -194.534)
  line L646 (36.6353, -194.534) -> (36.837, -194.257)
  line L647 (37.5362, -198.773) -> (37.2599, -198.569)
  line L648 (39.4987, -199.262) -> (39.1556, -199.274)
  line L649 (42.2758, -195.857) -> (42.295, -196.2)
  line L650 (40.1702, -199.124) -> (39.8383, -199.212)
  line L651 (37.0685, -194.003) -> (37.3268, -193.777)
  line L652 (38.4761, -199.184) -> (38.1481, -199.082)
  line L653 (39.1556, -199.274) -> (38.8133, -199.248)
  line L654 (42.0946, -197.292) -> (41.955, -197.606)
  line L655 (39.5841, -193.147) -> (39.9222, -193.206)
  line L656 (37.9107, -193.418) -> (38.229, -193.289)
  line L657 (36.7837, -198.076) -> (36.5898, -197.793)
  line L658 (36.2312, -195.477) -> (36.3304, -195.148)
  line L659 (37.8336, -198.945) -> (37.5362, -198.773)
  line L660 (40.4903, -199) -> (40.1702, -199.124)
  line L661 (41.4019, -194.033) -> (41.6299, -194.29)
  line L662 (40.7945, -198.841) -> (40.4903, -199)
  line L663 (172.031, -192.628) -> (171.732, -192.473)
  line L664 (173.393, -194.481) -> (173.297, -194.158)
  line L665 (173.464, -195.334) -> (173.47, -195.15)
  line L666 (172.798, -193.282) -> (172.568, -193.035)
  line L667 (171.089, -192.272) -> (170.755, -192.228)
  line L668 (172.568, -193.035) -> (172.311, -192.816)
  line L669 (172.997, -193.554) -> (172.798, -193.282)
  line L670 (172.676, -197.156) -> (172.892, -196.897)
  line L671 (171.561, -197.896) -> (171.87, -197.761)
  line L672 (173.345, -195.997) -> (173.424, -195.669)
  line L673 (173.164, -193.847) -> (172.997, -193.554)
  line L674 (172.311, -192.816) -> (172.031, -192.628)
  line L675 (171.87, -197.761) -> (172.161, -197.59)
  line L676 (173.077, -196.615) -> (173.229, -196.314)
  line L677 (173.229, -196.314) -> (173.345, -195.997)
  line L678 (172.892, -196.897) -> (173.077, -196.615)
  line L679 (170.417, -192.223) -> (170.082, -192.256)
  line L680 (172.161, -197.59) -> (172.431, -197.388)
  line L681 (172.431, -197.388) -> (172.676, -197.156)
  line L682 (171.416, -192.354) -> (171.089, -192.272)
  line L683 (173.297, -194.158) -> (173.164, -193.847)
  line L684 (170.755, -192.228) -> (170.417, -192.223)
  line L685 (173.47, -195.15) -> (173.451, -194.813)
  line L686 (171.732, -192.473) -> (171.416, -192.354)
  line L687 (173.424, -195.669) -> (173.464, -195.334)
  line L688 (173.451, -194.813) -> (173.393, -194.481)
  line L689 (170.082, -192.256) -> (169.752, -192.328)
  line L690 (37.0222, -194.262) -> (36.8141, -194.528)
  line L691 (173.415, -196.242) -> (173.275, -196.556)
  line L692 (167.551, -194.427) -> (167.65, -194.098)
  line L693 (167.489, -194.765) -> (167.551, -194.427)
  line L694 (37.8085, -193.632) -> (37.5227, -193.812)
  line L695 (171.888, -192.386) -> (172.188, -192.554)
  line L696 (171.158, -198.162) -> (170.819, -198.212)
  line L697 (168.856, -197.723) -> (168.58, -197.519)
  line L698 (170.571, -198.08) -> (170.907, -198.057)
  line L699 (169.796, -198.134) -> (169.468, -198.032)
  line L700 (42.15, -196.2) -> (42.1305, -195.863)
  line L701 (39.2507, -199.13) -> (39.5872, -199.107)
  line L702 (167.786, -193.783) -> (167.955, -193.484)
  line L703 (167.465, -195.107) -> (167.469, -195.058)
  line L704 (42.1305, -195.863) -> (42.0725, -195.531)
  line L705 (167.65, -194.098) -> (167.786, -193.783)
  line L706 (37.6501, -198.674) -> (37.9448, -198.838)
  line L707 (169.468, -198.032) -> (169.154, -197.895)
  line L708 (37.3761, -198.477) -> (37.6501, -198.674)
  line L709 (169.549, -192.239) -> (169.88, -192.147)
  line L710 (38.1129, -193.487) -> (37.8085, -193.632)
  line L711 (167.749, -196.44) -> (167.622, -196.121)
  line L712 (167.622, -196.121) -> (167.532, -195.789)
  line L713 (41.1112, -198.438) -> (41.3558, -198.206)
  line L714 (172.722, -192.983) -> (172.95, -193.24)
  line L715 (36.3215, -195.772) -> (36.2915, -196.108)
  line L716 (36.6378, -194.815) -> (36.4958, -195.121)
  line L717 (173.275, -196.556) -> (173.101, -196.852)
  line L718 (36.7138, -197.718) -> (36.9049, -197.996)
  line L719 (173.539, -194.469) -> (173.596, -194.807)
  line L720 (36.1597, -196.5) -> (36.1453, -196.157)
  line L721 (41.9767, -195.208) -> (41.8444, -194.897)
  line L722 (167.469, -195.058) -> (167.489, -194.765)
  line L723 (167.91, -196.743) -> (167.749, -196.44)
  line L724 (170.904, -192.097) -> (171.242, -192.156)
  line L725 (36.556, -197.42) -> (36.7138, -197.718)
  line L726 (40.4117, -193.523) -> (40.0962, -193.404)
  line L727 (170.819, -198.212) -> (170.476, -198.224)
  line L728 (171.242, -192.156) -> (171.572, -192.253)
  line L729 (36.3478, -196.779) -> (36.4334, -197.105)
  line L730 (172.188, -192.554) -> (172.467, -192.754)
  line L731 (41.5722, -197.947) -> (41.7574, -197.665)
  line L732 (168.929, -192.531) -> (169.231, -192.368)
  line L733 (172.467, -192.754) -> (172.722, -192.983)
  line L734 (40.5502, -198.811) -> (40.8414, -198.64)
  line L735 (36.2122, -196.839) -> (36.1597, -196.5)
  line L736 (39.769, -193.322) -> (39.4346, -193.278)
  line L737 (170.219, -192.092) -> (170.561, -192.075)
  line L738 (37.5227, -193.812) -> (37.2595, -194.023)
  line L739 (38.5808, -199.059) -> (38.9137, -199.114)
  line L740 (41.2479, -194.085) -> (40.9914, -193.866)
  line L741 (40.0962, -193.404) -> (39.769, -193.322)
  line L742 (173.614, -195.236) -> (173.585, -195.578)
  line L743 (168.58, -197.519) -> (168.328, -197.286)
  line L744 (173.444, -194.139) -> (173.539, -194.469)
  line L745 (169.901, -198.009) -> (170.234, -198.064)
  line L746 (169.154, -197.895) -> (168.856, -197.723)
  line L747 (41.6773, -194.604) -> (41.4776, -194.332)
  line L748 (167.48, -195.45) -> (167.465, -195.107)
  line L749 (170.907, -198.057) -> (171.239, -197.995)
  line L750 (38.2564, -198.967) -> (38.5808, -199.059)
  line L751 (173.596, -194.807) -> (173.615, -195.15)
  line L752 (170.234, -198.064) -> (170.571, -198.08)
  line L753 (171.239, -197.995) -> (171.561, -197.896)
  line L754 (36.8141, -194.528) -> (36.6378, -194.815)
  line L755 (169.88, -192.147) -> (170.219, -192.092)
  line L756 (168.157, -193.207) -> (168.389, -192.953)
  line L757 (41.8444, -194.897) -> (41.6773, -194.604)
  line L758 (38.9137, -199.114) -> (39.2507, -199.13)
  line L759 (169.265, -197.788) -> (169.576, -197.917)
  line L760 (172.896, -197.127) -> (172.661, -197.377)
  line L761 (37.2595, -194.023) -> (37.0222, -194.262)
  line L762 (170.561, -192.075) -> (170.904, -192.097)
  line L763 (168.328, -197.286) -> (168.104, -197.026)
  line L764 (39.9189, -199.045) -> (40.2413, -198.946)
  line L765 (173.101, -196.852) -> (172.896, -197.127)
  line L766 (36.1487, -196.108) -> (36.1692, -195.815)
  line L767 (39.4346, -193.278) -> (39.0973, -193.273)
  line L768 (172.399, -197.599) -> (172.115, -197.791)
  line L769 (41.4776, -194.332) -> (41.2479, -194.085)
  line L770 (39.0973, -193.273) -> (38.7617, -193.306)
  line L771 (42.0725, -195.531) -> (41.9767, -195.208)
  line L772 (42.1442, -196.384) -> (42.15, -196.2)
  line L773 (41.7574, -197.665) -> (41.909, -197.364)
  line L774 (168.389, -192.953) -> (168.647, -192.727)
  line L775 (172.661, -197.377) -> (172.399, -197.599)
  line L776 (37.1266, -198.25) -> (37.3761, -198.477)
  line L777 (169.576, -197.917) -> (169.901, -198.009)
  line L778 (168.225, -196.946) -> (168.447, -197.2)
  line L779 (168.696, -197.427) -> (168.97, -197.624)
  line L780 (172.115, -197.791) -> (171.81, -197.95)
  line L781 (40.8414, -198.64) -> (41.1112, -198.438)
  line L782 (36.3003, -196.445) -> (36.3478, -196.779)
  line L783 (167.532, -195.789) -> (167.48, -195.45)
  line L784 (36.1692, -195.815) -> (36.2312, -195.477)
  line L785 (36.4334, -197.105) -> (36.556, -197.42)
  line L786 (42.0249, -197.047) -> (42.1037, -196.719)
  line L787 (36.3899, -195.442) -> (36.3215, -195.772)
  line L788 (36.1453, -196.157) -> (36.1487, -196.108)
  line L789 (171.49, -198.074) -> (171.158, -198.162)
  line L790 (173.585, -195.578) -> (173.518, -195.915)
  line L791 (173.615, -195.15) -> (173.614, -195.236)
  line L792 (170.476, -198.224) -> (170.133, -198.198)
  line L793 (173.148, -193.52) -> (173.313, -193.821)
  line L794 (40.7115, -193.678) -> (40.4117, -193.523)
  line L795 (37.9448, -198.838) -> (38.2564, -198.967)
  line L796 (42.1037, -196.719) -> (42.1442, -196.384)
  line L797 (173.313, -193.821) -> (173.444, -194.139)
  line L798 (40.2413, -198.946) -> (40.5502, -198.811)
  line L799 (38.7617, -193.306) -> (38.4321, -193.378)
  line L800 (36.9049, -197.996) -> (37.1266, -198.25)
  line L801 (172.95, -193.24) -> (173.148, -193.52)
  line L802 (173.518, -195.915) -> (173.415, -196.242)
  line L803 (36.2915, -196.108) -> (36.3003, -196.445)
  line L804 (168.034, -196.668) -> (168.225, -196.946)
  line L805 (169.231, -192.368) -> (169.549, -192.239)
  line L806 (41.3558, -198.206) -> (41.5722, -197.947)
  line L807 (167.876, -196.37) -> (168.034, -196.668)
  line L808 (41.909, -197.364) -> (42.0249, -197.047)
  line L809 (168.97, -197.624) -> (169.265, -197.788)
  line L810 (171.572, -192.253) -> (171.888, -192.386)
  line L811 (167.668, -195.729) -> (167.753, -196.055)
  line L812 (167.955, -193.484) -> (168.157, -193.207)
  line L813 (168.447, -197.2) -> (168.696, -197.427)
  line L814 (39.5872, -199.107) -> (39.9189, -199.045)
  line L815 (171.81, -197.95) -> (171.49, -198.074)
  line L816 (36.3022, -197.171) -> (36.2122, -196.839)
  line L817 (168.104, -197.026) -> (167.91, -196.743)
  line L818 (167.753, -196.055) -> (167.876, -196.37)
  line L819 (38.4321, -193.378) -> (38.1129, -193.487)
  line L820 (168.647, -192.727) -> (168.929, -192.531)
  line L821 (40.9914, -193.866) -> (40.7115, -193.678)
  line L822 (170.133, -198.198) -> (169.796, -198.134)
  line L823 (36.4958, -195.121) -> (36.3899, -195.442)
  line L824 (168.843, -192.762) -> (168.579, -192.973)
  line L825 (169.752, -192.328) -> (169.433, -192.437)
  line L826 (169.433, -192.437) -> (169.128, -192.582)
  line L827 (168.579, -192.973) -> (168.342, -193.212)
  line L828 (168.342, -193.212) -> (168.134, -193.478)
  line L829 (169.128, -192.582) -> (168.843, -192.762)
  line L830 (168.134, -193.478) -> (167.958, -193.765)
  line L831 (38.6546, -50.9079) -> (38.3173, -50.9026)
  line L832 (35.5415, -53.402) -> (35.5115, -53.738)
  line L833 (37.8008, -56.6894) -> (38.1337, -56.7439)
  line L834 (35.9338, -55.3478) -> (36.1249, -55.6258)
  line L835 (35.5222, -54.8006) -> (35.4322, -54.4693)
  line L836 (38.1337, -56.7439) -> (38.4707, -56.7598)
  line L837 (38.989, -50.9519) -> (38.6546, -50.9079)
  line L838 (36.0341, -52.1578) -> (35.8578, -52.4454)
  line L839 (35.3687, -53.738) -> (35.3892, -53.4446)
  line L840 (35.4322, -54.4693) -> (35.3797, -54.1301)
  line L841 (35.3797, -54.1301) -> (35.3653, -53.7871)
  line L842 (36.5961, -56.107) -> (36.8701, -56.3038)
  line L843 (36.8701, -56.3038) -> (37.1648, -56.4679)
  line L844 (38.8072, -56.7369) -> (39.1389, -56.6754)
  line L845 (39.6317, -51.1534) -> (39.3162, -51.0341)
  line L846 (39.3162, -51.0341) -> (38.989, -50.9519)
  line L847 (41.129, -54.9936) -> (41.2449, -54.6769)
  line L848 (40.3312, -56.0679) -> (40.5758, -55.8357)
  line L849 (37.6521, -51.008) -> (37.3329, -51.1172)
  line L850 (35.8578, -52.4454) -> (35.7158, -52.7514)
  line L851 (35.6099, -53.0717) -> (35.5415, -53.402)
  line L852 (35.776, -55.0497) -> (35.9338, -55.3478)
  line L853 (39.9315, -51.3081) -> (39.6317, -51.1534)
  line L854 (40.8973, -52.2342) -> (40.6976, -51.9624)
  line L855 (41.3642, -54.014) -> (41.37, -53.83)
  line L856 (36.3466, -55.88) -> (36.5961, -56.107)
  line L857 (41.37, -53.83) -> (41.3505, -53.4932)
  line L858 (35.3892, -53.4446) -> (35.4512, -53.1069)
  line L859 (40.6976, -51.9624) -> (40.4679, -51.7153)
  line L860 (35.3653, -53.7871) -> (35.3687, -53.738)
  line L861 (40.7922, -55.5769) -> (40.9774, -55.295)
  line L862 (40.4679, -51.7153) -> (40.2114, -51.4962)
  line L863 (41.3505, -53.4932) -> (41.2925, -53.1609)
  line L864 (36.2422, -51.8924) -> (36.0341, -52.1578)
  line L865 (37.4764, -56.597) -> (37.8008, -56.6894)
  line L866 (40.2114, -51.4962) -> (39.9315, -51.3081)
  line L867 (37.1648, -56.4679) -> (37.4764, -56.597)
  line L868 (41.2925, -53.1609) -> (41.1967, -52.8375)
  line L869 (37.3329, -51.1172) -> (37.0285, -51.2625)
  line L870 (35.5203, -54.0752) -> (35.5678, -54.4091)
  line L871 (38.3173, -50.9026) -> (37.9817, -50.9361)
  line L872 (40.5758, -55.8357) -> (40.7922, -55.5769)
  line L873 (41.1967, -52.8375) -> (41.0644, -52.5272)
  line L874 (38.4707, -56.7598) -> (38.8072, -56.7369)
  line L875 (41.3237, -54.3489) -> (41.3642, -54.014)
  line L876 (37.9817, -50.9361) -> (37.6521, -51.008)
  line L877 (41.2449, -54.6769) -> (41.3237, -54.3489)
  line L878 (35.6534, -54.7354) -> (35.776, -55.0497)
  line L879 (37.0285, -51.2625) -> (36.7427, -51.4417)
  line L880 (39.7702, -56.4406) -> (40.0614, -56.2704)
  line L881 (40.9774, -55.295) -> (41.129, -54.9936)
  line L882 (35.5678, -54.4091) -> (35.6534, -54.7354)
  line L883 (36.7427, -51.4417) -> (36.4795, -51.6526)
  line L884 (40.0614, -56.2704) -> (40.3312, -56.0679)
  line L885 (39.1389, -56.6754) -> (39.4613, -56.5762)
  line L886 (35.7158, -52.7514) -> (35.6099, -53.0717)
  line L887 (35.5115, -53.738) -> (35.5203, -54.0752)
  line L888 (39.4613, -56.5762) -> (39.7702, -56.4406)
  line L889 (36.4795, -51.6526) -> (36.2422, -51.8924)
  line L890 (36.1249, -55.6258) -> (36.3466, -55.88)
  line L891 (41.0644, -52.5272) -> (40.8973, -52.2342)
  line L892 (37.6961, -56.8137) -> (37.3681, -56.7121)
  line L893 (36.4799, -56.1993) -> (36.228, -55.9661)
  line L894 (36.228, -55.9661) -> (36.0037, -55.7062)
  line L895 (36.0037, -55.7062) -> (35.8098, -55.4229)
  line L896 (37.3681, -56.7121) -> (37.0536, -56.5747)
  line L897 (38.0333, -56.878) -> (37.6961, -56.8137)
  line L898 (35.8098, -55.4229) -> (35.6486, -55.1198)
  line L899 (38.3756, -56.9043) -> (38.0333, -56.878)
  line L900 (36.7562, -56.4031) -> (36.4799, -56.1993)
  line L901 (35.6486, -55.1198) -> (35.5222, -54.8006)
  line L902 (37.0536, -56.5747) -> (36.7562, -56.4031)
  line L903 (38.7187, -56.8923) -> (38.3756, -56.9043)